Autodesk Fusion 360 part; units mm, degrees
(part 2 of 2)
equation "d270 = ( abs(pitch / 2 - ( 3.8 mm * 0.6 ) / 2) ) - webCenterOffset"
equation "d271 = abs(pitch - ( 0.55 mm ) / 2)"
equation "d272 = 3.8 mm * 0.6"
equation "d276 = frameZ"
equation "d278 = abs(pitch / 2 - 2.9 mm)"
equation "d279 = abs(pitch - 11 mm - 5 mm - 1 mm)"
equation "d284 = frameZ"
equation "d286 = abs(pitch / 2 - 2.9 mm)"
equation "d287 = abs(pitch - 11 mm + 5 mm - 1 mm)"
equation "d292 = carrierZ"
equation "d294 = abs(pitch / 2)"
equation "d295 = abs(pitch - 11 mm)"
equation "d296 = carrierBore"
equation "d297 = carrierThickness"
equation "d299 = carrierZ"
equation "d301 = abs(pitch / 2)"
equation "d302 = abs(pitch - 11 mm)"
equation "d303 = carrierHeadPocket"
equation "d304 = ( carrierHeadPocket - carrierBore ) / 2"
equation "d306 = carrierZ + 0.1 mm"
equation "d308 = abs(pitch / 2)"
equation "d309 = abs(pitch - 11 mm)"
equation "d311 = ( 9.2 mm - 5 mm ) / 2"
equation "d313 = carrierZ + 0.1 mm + ( 9.2 mm - 5 mm ) / 2"
equation "d315 = abs(pitch / 2)"
equation "d316 = abs(pitch - 11 mm)"
equation "d318 = 12 mm - ( 9.2 mm - 5 mm ) / 2"
equation "d320 = carrierZ + 0.1 mm"
equation "d322 = abs(pitch / 2 - ( 0.55 mm ) / 2)"
equation "d323 = abs(pitch - 11 mm - ( 9.2 mm * 0.6 ) / 2)"
equation "d325 = 9.2 mm * 0.6"
equation "d328 = carrierZ + 0.1 mm"
equation "d330 = abs(pitch / 2 - ( 9.2 mm * 0.6 ) / 2)"
equation "d331 = abs(pitch - 11 mm - ( 0.55 mm ) / 2)"
equation "d332 = 9.2 mm * 0.6"
equation "d336 = frameZ + profileLip"
equation "d338 = abs(pitch / 2 - nutWidth / 2)"
equation "d339 = abs(pitch - 11 mm - nutLength / 2)"
equation "d340 = nutWidth"
equation "d341 = nutLength"
equation "d342 = nutThickness"
equation "d344 = frameZ + profileLip"
equation "d346 = abs(pitch / 2)"
equation "d347 = abs(pitch - 11 mm)"
equation "d349 = nutThickness"
equation "d351 = carrierZ + 4 mm"
equation "d353 = ( abs(pitch / 2 - 2.15 mm) ) - webCenterOffset"
equation "d354 = abs(pitch + 2.5 mm)"
equation "d359 = carrierZ + 4.8 mm"
equation "d361 = ( abs(pitch / 2 - 2.15 mm) ) - webCenterOffset"
equation "d362 = abs(pitch + 3 mm)"
equation "d367 = carrierZ + 4 mm"
equation "d369 = ( abs(pitch / 2 - 2.15 mm) ) - webCenterOffset"
equation "d370 = abs(pitch + 3 mm)"
equation "d375 = carrierZ + 4 mm"
equation "d377 = ( abs(pitch / 2 + 1.65 mm) ) - webCenterOffset"
equation "d378 = abs(pitch + 3 mm)"
equation "d383 = ( ( pitch / 2 - 1.65 mm ) * 1.0 ) - webCenterOffset"
equation "d385 = abs(( carrierZ + 4.2 mm ) * -1)"
equation "d386 = abs(( pitch + 3 mm ) * 1)"
equation "d387 = abs(( pitch + 4.6 mm ) * 1)"
equation "d388 = abs(( carrierZ + 2.8 mm ) * -1)"
equation "d389 = abs(( pitch + 3.8 mm ) * 1)"
equation "d390 = ( ( 3.3 mm ) * 1.0 ) - webCenterOffset"
equation "webCenterOffset = ( slotHeight - slotWidth ) ^ 2 / ( 4 * pitch )" comment "Equal-distance M2 station for standard staggered lattice; preserve support axis"
equation "pixelGap = 0.4 mm" comment "v0.6.1 fit prototype; tune after physical testing"
equation "pixelThickness = 1.2 mm" comment "v0.6.1 fit prototype; tune after physical testing"
equation "tileBack = 1.2 mm" comment "v0.6.1 fit prototype; tune after physical testing"
equation "hookWidth = 3.2 mm" comment "v0.6.1 fit prototype; tune after physical testing"
equation "hookThroatGap = 0.2 mm" comment "v0.6.1 fit prototype; tune after physical testing"
equation "hookToeThickness = 2 mm" comment "v0.6.1 fit prototype; tune after physical testing"
equation "hookDrop = 3.5 mm" comment "v0.6.1 fit prototype; tune after physical testing"
equation "hookBearingY = -6.8 mm" comment "v0.6.1 fit prototype; tune after physical testing"
equation "hookStemHeight = 3 mm" comment "v0.6.1 fit prototype; tune after physical testing"
equation "hookToeOverlap = 1.7 mm" comment "v0.6.1 fit prototype; tune after physical testing"
equation "d403 = -tileBack"
equation "d405 = abs(60 mm - 4.5 mm)"
equation "d406 = abs(-9.5 mm)"
equation "d409 = tileBack"
equation "d411 = ( 60 mm - hookWidth / 2 ) * 1.0"
equation "d413 = abs(( hookBearingY ) * 1)"
equation "d414 = abs(( hookBearingY + hookStemHeight ) * 1)"
equation "d415 = abs(( boardThickness + hookThroatGap + hookToeThickness ) * -1)"
equation "d416 = abs(( -slotHeight / 2 - hookToeOverlap + 0.4 mm ) * 1)"
equation "d417 = abs(( boardThickness + hookThroatGap + hookToeThickness - 0.4 mm ) * -1)"
equation "d418 = abs(( -slotHeight / 2 - hookToeOverlap ) * 1)"
equation "d419 = abs(( boardThickness + hookThroatGap + 0.4 mm ) * -1)"
equation "d420 = abs(( boardThickness + hookThroatGap ) * -1)"
equation "d421 = ( hookWidth ) * 1.0"
equation "d423 = -tileBack - pixelThickness"
equation "d425 = abs(60 mm - 5 mm + pixelGap / 2)"
equation "d426 = abs(-10 mm + pixelGap / 2)"
equation "d427 = 10 mm - pixelGap"
equation "d428 = 10 mm - pixelGap"
equation "d429 = pixelThickness"
equation "d431 = -tileBack - pixelThickness"
equation "d433 = abs(60 mm - 5 mm + pixelGap / 2)"
equation "d434 = abs(pixelGap / 2)"
equation "d435 = 10 mm - pixelGap"
equation "d436 = 10 mm - pixelGap"
equation "d437 = pixelThickness"
